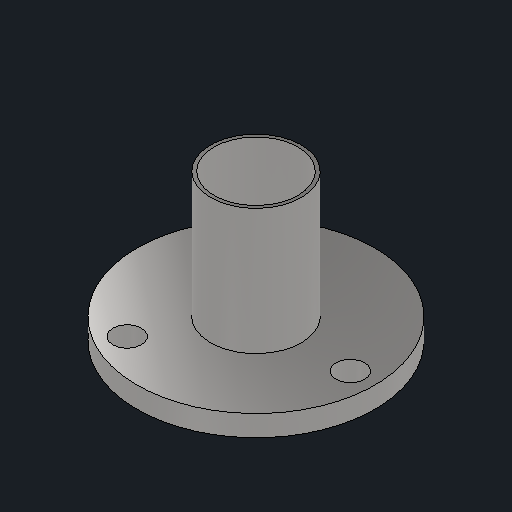
# Autodesk Inventor part: Screen-membrane
Saved by Autodesk Inventor 2027.1 (Build 311270010, 270A)
## iProperties
Created: 2026-08-19
Part Number: Screen-membrane
Material: ステンレス鋼
Document SubType Name: Modeling
Designer: rkawa
Density: 8 g/cm^3
Appearance: 半つや出し
Mass: 20.9526 g
Surface Area: 34.7361 cm^2
Volume: 2.61908 cm^3
Author: rkawa
Autodesk Inventor part; units mm, degrees
ref_plane "YZ Plane" through (0, 0, 0) normal (1, 0, 0) x (0, 1, 0)
ref_plane "XZ Plane" through (0, 0, 0) normal (0, 1, 0) x (-1, 0, 0)
ref_plane "XY Plane" through (0, 0, 0) normal (0, 0, 1) x (1, 0, 0)
sketch "スケッチ1" plane through (0, 0, 0) normal (0, 1, 0) x (-1, 0, 0)
  circle A0 centre (0, 0) radius 17
  circle A1 centre (0, 0) radius 6
  dimension "d0" = 34
  dimension "d1" = 12
  constraints: 2 centre point, 2 coincident
  measures "d0" diameter of A0
  measures "d1" diameter of A1
extrude "押し出し1" add sketch "スケッチ1" along normal blind 3
sketch "スケッチ2" plane through (0, 3, 0) normal (0, 1, 0) x (1, 0, 0)
  circle A0 centre (0, 0) radius 6.5
  circle A1 centre (0, 0) radius 6 projected
  dimension "d4" = 13
  constraints: 1 centre point, 1 coincident
  measures "d4" diameter of A0
extrude "押し出し2" add sketch "スケッチ2" along normal blind 18
sketch "スケッチ3" plane through (0, 0, 0) normal (0, -1, 0) x (1, 0, 0)
  circle A0 centre (0, 0) radius 13.5
  point P0 (13.5, 0)
  point P1 (-6.75, 11.6913)
  point P2 (-6.75, -11.6913)
  dimension "d7" = 27
  dimension "d10" = 360
  constraints: 1 coincident, 1 horizontal alignment, 6 other
hole "穴1" at (13.5, 0, 0) at (-6.75, 0, 11.6913) at (-6.75, 0, -11.6913) direction (0, 1, 0) diameter 4.1 end through all
